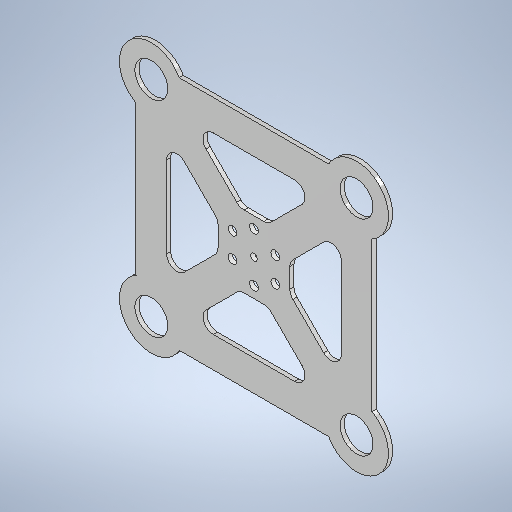
# Autodesk Inventor part: plate50-4
Saved by Autodesk Inventor 2025.3 (Build 293356000, 356)
## iProperties
Created: 2026-09-19
Part Number: plate50-4
Material: アルミニウム 5052 H32
Document SubType Name: Modeling
Designer: yunto
Density: 2.68 g/cm^3
Appearance: サテン
Author: yunto
Autodesk Inventor part; units mm, degrees
ref_plane "YZ Plane" through (0, 0, 0) normal (1, 0, 0) x (0, 1, 0)
ref_plane "XZ Plane" through (0, 0, 0) normal (0, 1, 0) x (-1, 0, 0)
ref_plane "XY Plane" through (0, 0, 0) normal (0, 0, 1) x (1, 0, 0)
sketch "スケッチ1" plane through (0, 0, 0) normal (0, 0, 1) x (1, 0, 0)
  line L0 (50, -50) -> (-50, -50) construction
  line L1 (-50, -50) -> (-50, 50) construction
  line L2 (-50, 50) -> (50, 50) construction
  line L3 (50, 50) -> (50, -50) construction
  line L4 (50, -50) -> (-50, 50) construction
  line L5 (-50, -50) -> (50, 50) construction
  circle A0 centre (-50, 50) radius 8
  circle A1 centre (50, 50) radius 8
  circle A2 centre (-50, -50) radius 8
  circle A3 centre (50, -50) radius 8
  circle A4 centre (-50, 50) radius 15.5
  circle A5 centre (-50, -50) radius 15.5
  circle A6 centre (50, -50) radius 15.5
  circle A7 centre (50, 50) radius 15.5
  line L6 (57.5, -57.5) -> (-57.5, -57.5)
  line L7 (-57.5, -57.5) -> (-57.5, 57.5)
  line L8 (-57.5, 57.5) -> (57.5, 57.5)
  line L9 (57.5, 57.5) -> (57.5, -57.5)
  line L10 (57.5, -57.5) -> (-57.5, 57.5) construction
  line L11 (-57.5, -57.5) -> (57.5, 57.5) construction
  line L12 (0, 0) -> (0, 57.5) construction
  line L13 (-31.8934, 42.5) -> (31.8934, 42.5)
  line L14 (31.8934, 42.5) -> (0, 10.6066)
  line L15 (0, 10.6066) -> (-31.8934, 42.5)
  line L16 (-42.5, -31.8934) -> (-42.5, 31.8934)
  line L17 (-10.6066, 0) -> (-42.5, -31.8934)
  line L18 (-42.5, 31.8934) -> (-10.6066, 0)
  line L19 (31.8934, -42.5) -> (-31.8934, -42.5)
  line L20 (0, -10.6066) -> (31.8934, -42.5)
  line L21 (-31.8934, -42.5) -> (0, -10.6066)
  line L22 (42.5, 31.8934) -> (42.5, -31.8934)
  line L23 (10.6066, 0) -> (42.5, 31.8934)
  line L24 (42.5, -31.8934) -> (10.6066, 0)
  line L25 (-17.5, 17.5) -> (17.5, 17.5)
  line L26 (17.5, 17.5) -> (17.5, -17.5)
  line L27 (17.5, -17.5) -> (-17.5, -17.5)
  line L28 (-17.5, -17.5) -> (-17.5, 17.5)
  line L29 (-17.5, 17.5) -> (17.5, -17.5) construction
  line L30 (17.5, 17.5) -> (-17.5, -17.5) construction
  point P0 (0, 42.5)
  point P1 (-42.5, 0)
  point P2 (0, -42.5)
  point P3 (42.5, 0)
  point P4 (-36.4353, -57.5)
  point P5 (36.4353, -57.5)
  point P6 (57.5, -36.4353)
  point P7 (57.5, 36.4353)
  point P8 (36.4353, 57.5)
  point P9 (-36.4353, 57.5)
  point P10 (-57.5, 36.4353)
  point P11 (-57.5, -36.4353)
  point P12 (-52.7839, -57.5)
  point P13 (-57.5, -52.7839)
  point P14 (57.5, -52.7839)
  point P15 (52.7839, -57.5)
  point P16 (-57.5, 52.7839)
  point P17 (-52.7839, 57.5)
  point P18 (52.7839, 57.5)
  point P19 (57.5, 52.7839)
  point P20 (-17.5, 6.8934)
  point P21 (-17.5, -6.8934)
  point P22 (-6.8934, 17.5)
  point P23 (6.8934, 17.5)
  point P24 (17.5, 6.8934)
  point P25 (6.8934, -17.5)
  point P26 (-6.8934, -17.5)
  point P27 (-22.0711, -15)
  point P28 (-22.0711, 15)
  point P29 (22.0711, 15)
  point P30 (22.0711, -15)
  point P31 (17.5, -6.8934)
  dimension "d0" = 31
  dimension "d1" = 16
  dimension "d2" = 100
  dimension "d5" = 360
  dimension "d7" = 15
  dimension "d8" = 15
  dimension "d9" = 7.5
  dimension "d15" = 35
  dimension "d17" = 35
  constraints: 62 end point, 9 coincident, 8 centre point, 8 midpoint, 7 parallel, 6 equal radius, 4 horizontal, 4 perpendicular, 3 point on line, 29 other
  measures "d0" diameter of A4
  measures "d1" diameter of A0
  measures "d2" distance of A1.centre L1.end
  measures "d7" distance between parallel lines of L18 L15
  measures "d8" distance between parallel lines of L8 L13
  measures "d9" distance between parallel lines of L8 L2
  measures "d15" distance of L25.end L26.end
  measures "d17" distance of L25.start L25.end
extrude "押し出し1" add sketch "スケッチ1" along normal blind 2 contours A0 L8 A4 L7 | A0 L8 L7 A4 | A0 L7 L8 | L8 A7 L9 A6 L6 A5 L7 A4 | L8 A1 L9 A7 | A7 L9 A1 L8 | L7 A2 L6 A5 | A5 L6 A2 L7 | L9 A3 L6 A6 | A6 L6 A3 L9 | L8 L9 A1 | A2 L6 L7 | L9 L6 A3 | L25 L14 L15 | L15 L14 L25 L26 L23 L24 L27 L20 L21 L28 L17 L18 | L18 L17 L28 | L26 L24 L23 | L21 L20 L27 picked at (-56.6301, 55.8256) picked at (55.8256, 56.6301) picked at (-56.6301, -55.8256) picked at (55.8256, -56.6301)
fillet "フィレット1" radius 5 16 edges at (-42.5, -31.8934, 1) (-31.8934, -42.5, 1) (-42.5, 31.8934, 1) (-31.8934, 42.5, 1) (42.5, -31.8934, 1) (31.8934, -42.5, 1) (42.5, 31.8934, 1) (31.8934, 42.5, 1) (-17.5, 6.8934, 1) (-17.5, -6.8934, 1) (-6.8934, 17.5, 1) (6.8934, 17.5, 1) (17.5, 6.8934, 1) (17.5, -6.8934, 1) (6.8934, -17.5, 1) (-6.8934, -17.5, 1)
sketch "スケッチ2" plane through (0, 0, 0) normal (0, 0, -1) x (-1, 0, 0)
  circle A0 centre (0, 0) radius 1.6
  circle A1 centre (0, 12) radius 2.1
  circle A2 centre (0, 0) radius 12 construction
  line L0 (0, 12) -> (0, -12) construction
  line L1 (0, 0) -> (-12, 0) construction
  circle A3 centre (0, 0) radius 5
  circle A4 centre (0, 0) radius 14
  circle A5 centre (-10.3923, 6) radius 2.1
  circle A6 centre (-10.3923, -6) radius 2.1
  circle A7 centre (0, -12) radius 2.1
  circle A8 centre (10.3923, -6) radius 2.1
  circle A9 centre (10.3923, 6) radius 2.1
  point P0 (0, 14)
  dimension "d22" = 28
  dimension "d18" = 4.2
  dimension "d19" = 3.2
  dimension "d20" = 24
  dimension "d21" = 10
  dimension "d27" = 360
  constraints: 9 centre point, 5 coincident, 4 end point, 3 point on circle, 1 horizontal, 1 midpoint, 1 perpendicular, 1 point on line, 1 vertical alignment, 15 other
  measures "d18" diameter of A1
  measures "d19" diameter of A0
  measures "d20" diameter of A2
  measures "d21" diameter of A3
extrude "押し出し2" cut sketch "スケッチ2" against normal blind 3 contours A0 | A1 A4 | A4 A1 | A9 A4 | A4 A9 | A5 A4 | A4 A5 | A6 A4 | A4 A6 | A8 A4 | A4 A8 | A7 A4 | A4 A7
equation "\"d0\" = d1 + 2 * d9"
equation "\"d2\" = padpitch"
equation "\"d8\" = d7"
equation "\"d9\" = 0.5 * d8"
equation "\"d17\" = d15"
equation "\"pitchLength\" = 65"
equation "\"pRSdeg\" = 30deg"
equation "\"handDeg\" = 60deg"
equation "\"padpitch\" = 100"
